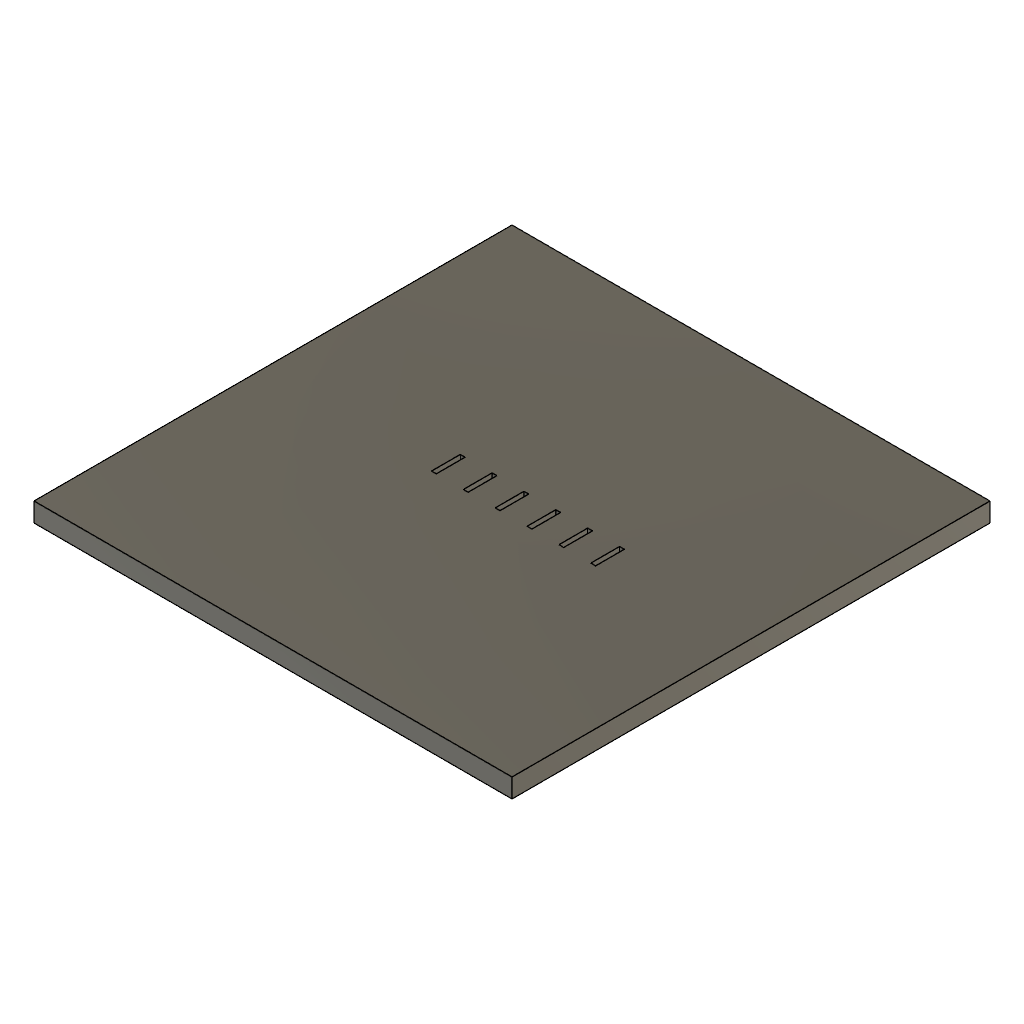
sym_extent_q6 (Autodesk Fusion 360 design; units mm, degrees)
Autodesk Fusion 360 part; units mm, degrees
sketch "Sketch1" plane through (0, 0, 0) normal (0, 0, 1) x (1, 0, 0)
  line L0 (-50, -50) -> (50, -50)
  line L1 (50, -50) -> (50, 50)
  line L2 (50, 50) -> (-50, 50)
  line L3 (-50, 50) -> (-50, -50)
extrude "Extrude1" add sketch "Sketch1" along normal blind 4
ref_plane "WorkPlane1" through (0, 0, 4) normal (0, 0, 1) x (1, 0, 0)
sketch "Sketch2" plane through (0, 0, 4) normal (0, 0, 1) x (1, 0, 0)
  line L0 (-0.5, -3) -> (0.5, -3)
  line L1 (0.5, -3) -> (0.5, 3)
  line L2 (0.5, 3) -> (-0.5, 3)
  line L3 (-0.5, 3) -> (-0.5, -3)
extrude "Extrude2" cut sketch "Sketch2" against normal blind 1
pattern_linear "R-Pattern1" count 6 spacing 6.6667 along (1, 0, 0) both ways of "Extrude2"
named bodies: "Plate"
